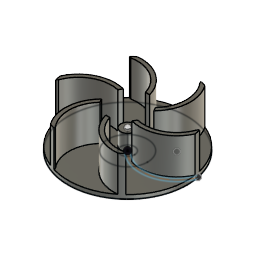
impeller (Autodesk Fusion 360 design; units mm, degrees)
Autodesk Fusion 360 part; units mm, degrees
sketch "Skizze1" plane through (0, 0, 0) normal (0, 0, 1) x (1, 0, 0)
  circle A0 centre (0, 0) radius 30
  arc A1 (0.7294, 0.684) -> (28.4153, 6.5037) centre (12.8039, 12.0069) ccw
  arc A2 (0.7294, 0.684) -> (-0.7294, -0.684) centre (0, 0) ccw
  arc A3 (-0.7294, -0.684) -> (30.3015, 5.8388) centre (12.8039, 12.0069) ccw
  arc A4 (30.3015, 5.8388) -> (28.4153, 6.5037) centre (29.3584, 6.1712) ccw
  arc A5 (0, 0) -> (29.3584, 6.1712) centre (12.8039, 12.0069) ccw construction
  circle A6 centre (0, 0) radius 1
  circle A7 centre (0, 0) radius 3.5
  circle A8 centre (0, 0) radius 10
  dimension "d1" = 60
  dimension "d10" = 2
  dimension "d14" = 2
  dimension "d27" = 20
  dimension "d28" = 7
  constraint coincident A0.centre A2.centre
  constraint tangent A1 A2
  constraint tangent A2 A3
  constraint tangent A3 A4
  constraint tangent A1 A4
  constraint coincident A0 A4.centre
  constraint concentric A0 A6
  constraint concentric A2 A7
  constraint concentric A2 A8
  measures "d1" diameter of A0
  measures "d10" diameter of A6
  measures "d14" distance of A1 A3
  measures "d27" diameter of A8
  measures "d28" diameter of A7
sketch "Skizze2" plane through (0, 0, 0) normal (0, 1, 0) x (1, 0, 0)
  line L0 (0, -10) -> (0, 0)
  constraint coincident L0.end origin
  constraint vertical L0
extrude "Extrusion7" add sketch "Skizze1" along normal blind 20 contours A0 A1 A3 A4 A8 picked at (25.5307, -0.5175) makes body 1
pattern_circular "C-Anordnung2" count 6 over 360 about axis through (0, 0, 10) along (0, 0, -1) of bodies 1 makes body 2 at (1.9038, -16.1444, 13.3333) makes body 3 at (-11.5929, -27.1512, 13.3333) makes body 4 at (-27.964, -1.3119, 13.3333) makes body 5 at (-0.5043, 13.9538, 13.3333) makes body 6 at (11.5929, 27.1512, 13.3333)
extrude "Extrusion8" add sketch "Skizze1" along normal blind 2 contours A0 A1 A3 A4 A8 | A0 A1 A3 A4 A8 | A1 A3 A7 A8 | A1 A3 A7 A8 bodies 1 2 3 4 5 6
extrude "Extrusion9" add sketch "Skizze1" along normal blind 10 contours A1 A2 A3 A6 A7 | A1 A3 A6 A7 bodies 1
